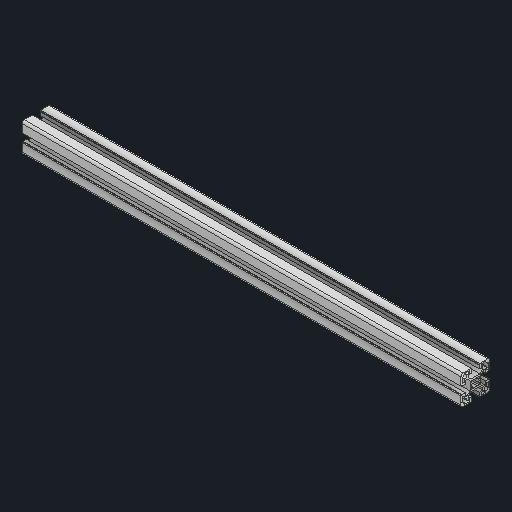
# Autodesk Inventor part: 3842993724_STRUT PROFILE 40x40L_h150_260914151227681
Saved by Autodesk Inventor 2026 (Build 300175050, 175E)
## iProperties
Created: 2026-07-02
Material: Generic
Document SubType Name: Modeling
Designer: Anura
Density: 1 g/cm^3
Appearance: Default
Catalog Web Link: www.boschrexroth.com/brl
Description: STRUT PROFILE 40x40L
Vendor: Bosch Rexroth AG - BRL
Mass: 900 g
Package size: 1
Material no.: 3842993724.0
Part name: STRUT PROFILE 40x40L
Parameters: LP=605MM;
Weight: 0.9075
Product group: MGE
HS code: 76042100.0
Format Version: 0
MTproCodeNo: 76042100.0
MTproDesignation: STRUT PROFILE 40x40L
MTproParam1: 2#0@Profile type=40x40L|Length L [mm]=605|Number of finishes=0|
MtproPline: 20
MTproPrice: 0.0
MTproWeight: 0.9075
MtproWeightUnit: kg/m
Major Version: 4
Minor Version: 0
OrderNo: 3842993724.0
Param: LP=605MM;
ProductId: Bosch Rexroth AG
Sending System: Bosch Rexroth AG
FileDetail: HD
Author: Anura
Autodesk Inventor part; units mm, degrees
ref_plane "YZ Plane" through (0, 0, 0) normal (1, 0, 0) x (0, 1, 0)
ref_plane "XZ Plane" through (0, 0, 0) normal (0, 1, 0) x (-1, 0, 0)
ref_plane "XY Plane" through (0, 0, 0) normal (0, 0, 1) x (1, 0, 0)
sketch "Sketch1" plane through (0, 0, 0) normal (1, 0, 0) x (0, 1, 0)
  line L0 (15.5, -8) -> (18.5, -8)
  line L1 (18.5, -8) -> (18.5, -14.5)
  line L2 (18.5, -14.5) -> (17.25, -14.5)
  arc A0 (14.5, -17.25) -> (17.25, -14.5) centre (14.5, -14.5) ccw
  line L3 (14.5, -17.25) -> (14.5, -18.5)
  line L4 (14.5, -18.5) -> (8, -18.5)
  line L5 (8, -18.5) -> (8, -15.5)
  line L6 (8, -15.5) -> (11.75, -15.5)
  line L7 (11.75, -15.5) -> (11.75, -14.5)
  arc A1 (14.5, -11.75) -> (11.75, -14.5) centre (14.5, -14.5) ccw
  line L8 (14.5, -11.75) -> (15.5, -11.75)
  line L9 (15.5, -11.75) -> (15.5, -8)
  line L10 (-15.5, -8) -> (-15.5, -11.75)
  line L11 (-15.5, -11.75) -> (-14.5, -11.75)
  arc A2 (-11.75, -14.5) -> (-14.5, -11.75) centre (-14.5, -14.5) ccw
  line L12 (-11.75, -14.5) -> (-11.75, -15.5)
  line L13 (-11.75, -15.5) -> (-8, -15.5)
  line L14 (-8, -15.5) -> (-8, -18.5)
  line L15 (-8, -18.5) -> (-14.5, -18.5)
  line L16 (-14.5, -18.5) -> (-14.5, -17.25)
  arc A3 (-17.25, -14.5) -> (-14.5, -17.25) centre (-14.5, -14.5) ccw
  line L17 (-17.25, -14.5) -> (-18.5, -14.5)
  line L18 (-18.5, -14.5) -> (-18.5, -8)
  line L19 (-18.5, -8) -> (-15.5, -8)
  line L20 (8, 15.5) -> (8, 18.5)
  line L21 (8, 18.5) -> (14.5, 18.5)
  line L22 (14.5, 18.5) -> (14.5, 17.25)
  arc A4 (17.25, 14.5) -> (14.5, 17.25) centre (14.5, 14.5) ccw
  line L23 (17.25, 14.5) -> (18.5, 14.5)
  line L24 (18.5, 14.5) -> (18.5, 8)
  line L25 (18.5, 8) -> (15.5, 8)
  line L26 (15.5, 8) -> (15.5, 11.75)
  line L27 (15.5, 11.75) -> (14.5, 11.75)
  arc A5 (11.75, 14.5) -> (14.5, 11.75) centre (14.5, 14.5) ccw
  line L28 (11.75, 14.5) -> (11.75, 15.5)
  line L29 (11.75, 15.5) -> (8, 15.5)
  line L30 (-14.5, 11.75) -> (-15.5, 11.75)
  line L31 (-15.5, 11.75) -> (-15.5, 8)
  line L32 (-15.5, 8) -> (-18.5, 8)
  line L33 (-18.5, 8) -> (-18.5, 14.5)
  line L34 (-18.5, 14.5) -> (-17.25, 14.5)
  arc A6 (-14.5, 17.25) -> (-17.25, 14.5) centre (-14.5, 14.5) ccw
  line L35 (-14.5, 17.25) -> (-14.5, 18.5)
  line L36 (-14.5, 18.5) -> (-8, 18.5)
  line L37 (-8, 18.5) -> (-8, 15.5)
  line L38 (-8, 15.5) -> (-11.75, 15.5)
  line L39 (-11.75, 15.5) -> (-11.75, 14.5)
  arc A7 (-14.5, 11.75) -> (-11.75, 14.5) centre (-14.5, 14.5) ccw
  line L40 (-5.2, 5.2) -> (-2.261, 5.2)
  line L41 (-2.261, 5.2) -> (-1.9937, 4.5853)
  arc A8 (1.9937, 4.5853) -> (-1.9937, 4.5853) centre (0, 0) ccw
  line L42 (1.9937, 4.5853) -> (2.261, 5.2)
  line L43 (2.261, 5.2) -> (5.2, 5.2)
  line L44 (5.2, 5.2) -> (5.2, 2.261)
  line L45 (5.2, 2.261) -> (4.5853, 1.9937)
  arc A9 (4.5853, -1.9937) -> (4.5853, 1.9937) centre (0, 0) ccw
  line L46 (4.5853, -1.9937) -> (5.2, -2.261)
  line L47 (5.2, -2.261) -> (5.2, -5.2)
  line L48 (5.2, -5.2) -> (2.261, -5.2)
  line L49 (2.261, -5.2) -> (1.9937, -4.5853)
  arc A10 (-1.9937, -4.5853) -> (1.9937, -4.5853) centre (0, 0) ccw
  line L50 (-1.9937, -4.5853) -> (-2.261, -5.2)
  line L51 (-2.261, -5.2) -> (-5.2, -5.2)
  line L52 (-5.2, -5.2) -> (-5.2, -2.261)
  line L53 (-5.2, -2.261) -> (-4.5853, -1.9937)
  arc A11 (-4.5853, 1.9937) -> (-4.5853, -1.9937) centre (0, 0) ccw
  line L54 (-4.5853, 1.9937) -> (-5.2, 2.261)
  line L55 (-5.2, 2.261) -> (-5.2, 5.2)
  line L56 (11.4642, 10.05) -> (14, 10.05)
  line L57 (14, 10.05) -> (14, 5)
  line L58 (14, 5) -> (18.5, 5)
  line L59 (18.5, 5) -> (18.5, 5.8)
  line L60 (18.5, 5.8) -> (20, 5.8)
  line L61 (20, 5.8) -> (20, 17)
  arc A12 (20, 17) -> (17, 20) centre (17, 17) ccw
  line L62 (17, 20) -> (5.8, 20)
  line L63 (5.8, 20) -> (5.8, 18.5)
  line L64 (5.8, 18.5) -> (5, 18.5)
  line L65 (5, 18.5) -> (5, 14)
  line L66 (5, 14) -> (10.05, 14)
  line L67 (10.05, 14) -> (10.05, 11.4642)
  line L68 (10.05, 11.4642) -> (6.0858, 7.5)
  line L69 (6.0858, 7.5) -> (-6.0858, 7.5)
  line L70 (-6.0858, 7.5) -> (-10.05, 11.4642)
  line L71 (-10.05, 11.4642) -> (-10.05, 14)
  line L72 (-10.05, 14) -> (-5, 14)
  line L73 (-5, 14) -> (-5, 18.5)
  line L74 (-5, 18.5) -> (-5.8, 18.5)
  line L75 (-5.8, 18.5) -> (-5.8, 20)
  line L76 (-5.8, 20) -> (-17, 20)
  arc A13 (-17, 20) -> (-20, 17) centre (-17, 17) ccw
  line L77 (-20, 17) -> (-20, 5.8)
  line L78 (-20, 5.8) -> (-18.5, 5.8)
  line L79 (-18.5, 5.8) -> (-18.5, 5)
  line L80 (-18.5, 5) -> (-14, 5)
  line L81 (-14, 5) -> (-14, 10.05)
  line L82 (-14, 10.05) -> (-11.4642, 10.05)
  line L83 (-11.4642, 10.05) -> (-7.5, 6.0858)
  line L84 (-7.5, 6.0858) -> (-7.5, -6.0858)
  line L85 (-7.5, -6.0858) -> (-11.4642, -10.05)
  line L86 (-11.4642, -10.05) -> (-14, -10.05)
  line L87 (-14, -10.05) -> (-14, -5)
  line L88 (-14, -5) -> (-18.5, -5)
  line L89 (-18.5, -5) -> (-18.5, -5.8)
  line L90 (-18.5, -5.8) -> (-20, -5.8)
  line L91 (-20, -5.8) -> (-20, -17)
  arc A14 (-20, -17) -> (-17, -20) centre (-17, -17) ccw
  line L92 (-17, -20) -> (-5.8, -20)
  line L93 (-5.8, -20) -> (-5.8, -18.5)
  line L94 (-5.8, -18.5) -> (-5, -18.5)
  line L95 (-5, -18.5) -> (-5, -14)
  line L96 (-5, -14) -> (-10.05, -14)
  line L97 (-10.05, -14) -> (-10.05, -11.4642)
  line L98 (-10.05, -11.4642) -> (-6.0858, -7.5)
  line L99 (-6.0858, -7.5) -> (6.0858, -7.5)
  line L100 (6.0858, -7.5) -> (10.05, -11.4642)
  line L101 (10.05, -11.4642) -> (10.05, -14)
  line L102 (10.05, -14) -> (5, -14)
  line L103 (5, -14) -> (5, -18.5)
  line L104 (5, -18.5) -> (5.8, -18.5)
  line L105 (5.8, -18.5) -> (5.8, -20)
  line L106 (5.8, -20) -> (17, -20)
  arc A15 (17, -20) -> (20, -17) centre (17, -17) ccw
  line L107 (20, -17) -> (20, -5.8)
  line L108 (20, -5.8) -> (18.5, -5.8)
  line L109 (18.5, -5.8) -> (18.5, -5)
  line L110 (18.5, -5) -> (14, -5)
  line L111 (14, -5) -> (14, -10.05)
  line L112 (14, -10.05) -> (11.4642, -10.05)
  line L113 (11.4642, -10.05) -> (7.5, -6.0858)
  line L114 (7.5, -6.0858) -> (7.5, 6.0858)
  line L115 (7.5, 6.0858) -> (11.4642, 10.05)
  constraints: 232 end point, 32 point on circle, 16 centre point
extrude "BR_Extrude" add sketch "Sketch1" along normal blind 320 and the other way blind 285
equation "\"extrude_1\" = 0.5 * BR_WP2_BR_WP4_Length_090614421478226 + Start_delta"
equation "\"extrude_2\" = 0.5 * BR_WP2_BR_WP4_Length_090614421478226 + End_delta"
equation "\"End_delta\" = -15"
equation "\"BR_WP2_BR_WP4_Length_090614421478226\" = 600"
equation "\"Start_delta\" = 20"
body "Solid1"
